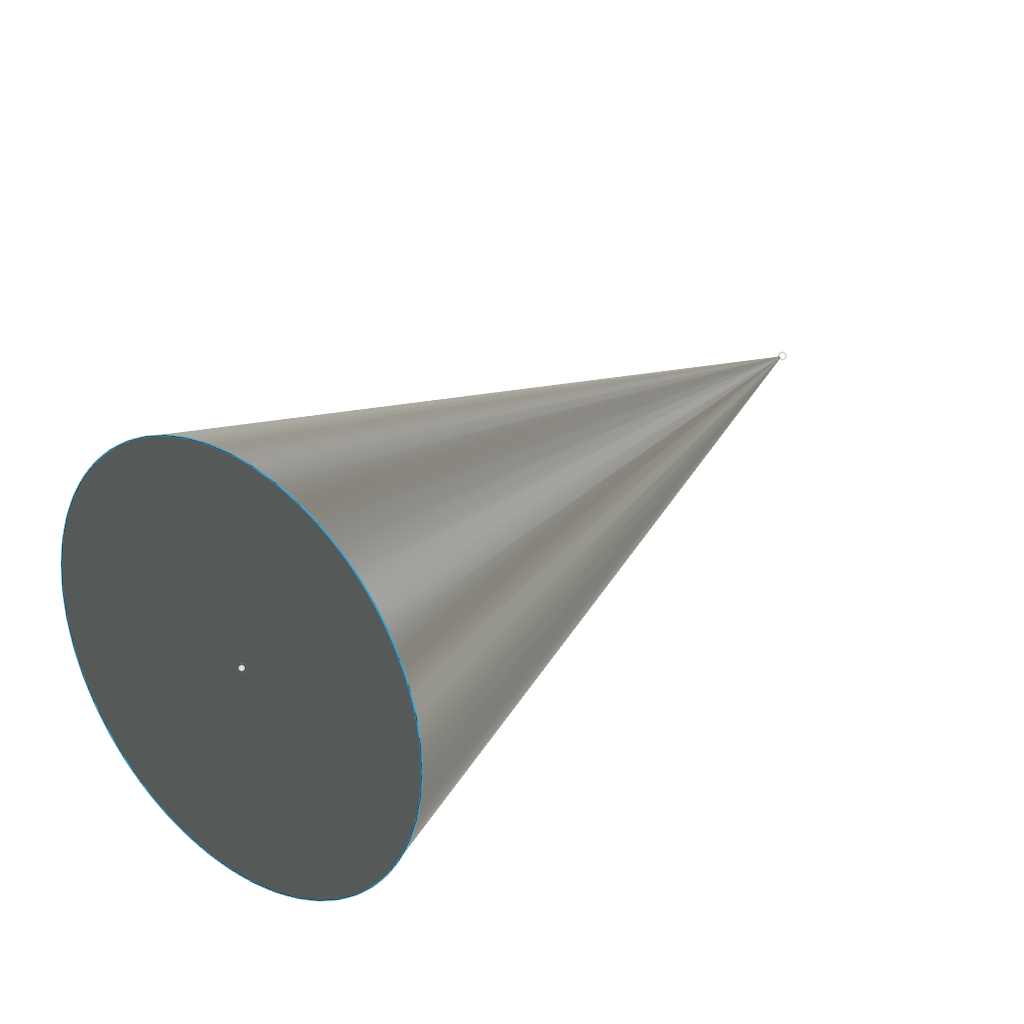
sharp_start (Autodesk Fusion 360 design; units mm, degrees)
part number: 2026-10-20-22-17-13-249
Autodesk Fusion 360 part; units mm, degrees
sketch "LoftPointSection1" plane through (0, 0, 0) normal (0, 0, 1) x (1, 0, 0)
ref_plane "WorkPlane1" through (0, 0, 30) normal (0, 0, 1) x (1, 0, 0)
sketch "LoftPointSection2" plane through (0, 0, 30) normal (0, 0, 1) x (1, 0, 0)
  circle A0 centre (0, 0) radius 10
loft "ProbeLoftPoint" add profiles "LoftPointSection2" section 1 point at (0, 0, 0) section 2
